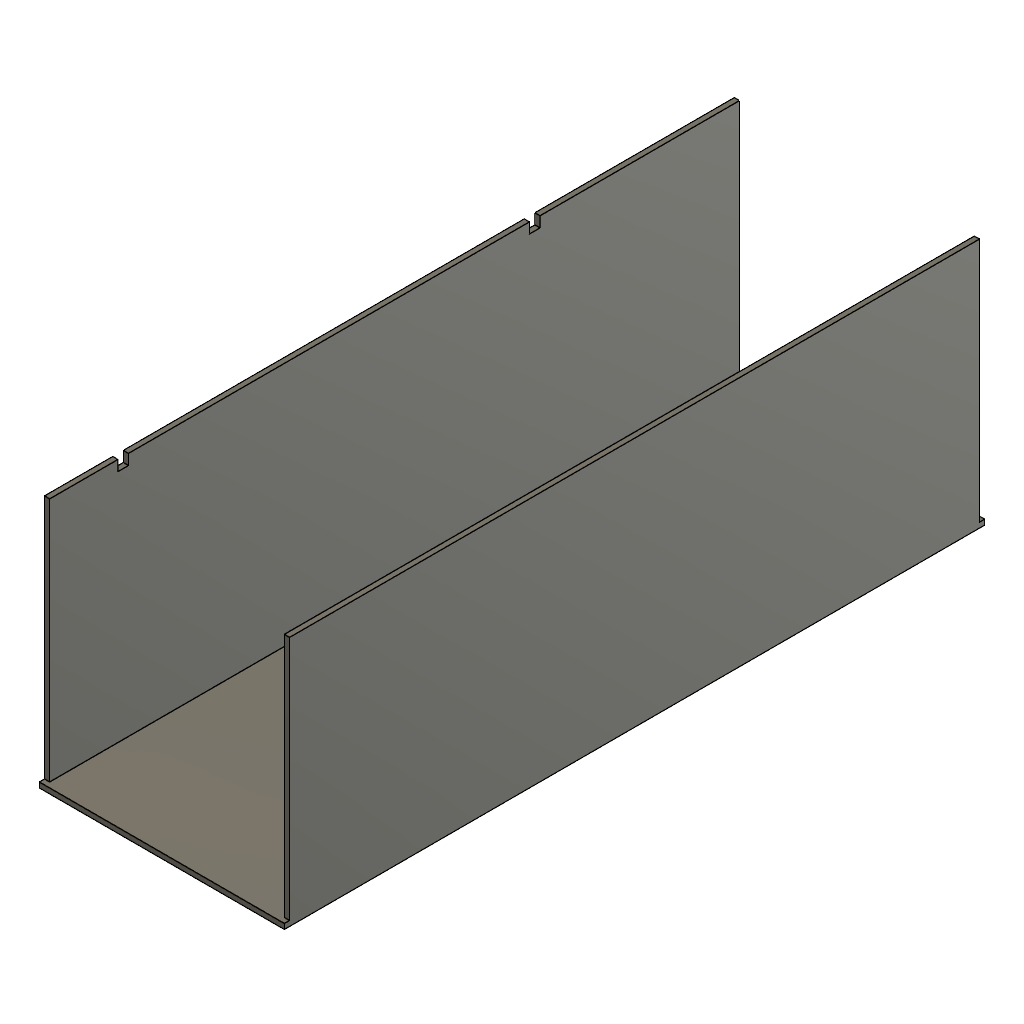
cooling-enclosure-assembly (Autodesk Fusion 360 archive; units mm, degrees)
design "Enclosure Base"
part number: 2026-11-27-19-35-51-728
Autodesk Fusion 360 part; units mm, degrees
sketch "Sketch1" plane through (0, 0, 0) normal (0, 1, 0) x (1, 0, 0)
  line L0 (70, 200) -> (-70, 200)
  line L1 (-70, 200) -> (-70, -200)
  line L2 (-70, -200) -> (70, -200)
  line L3 (70, -200) -> (70, 200)
  line L4 (70, 200) -> (-70, -200) construction
  line L5 (-70, 200) -> (70, -200) construction
  dimension "d1" = 140
  dimension "d2" = 400
  constraint horizontal L0
  constraint perpendicular L0 L1
  constraint parallel L0 L2
  constraint parallel L1 L3
  constraint coincident L4 origin
  constraint coincident L5 origin
  measures "d1" distance of L1.end L2.end
extrude "Extrude1" add sketch "Sketch1" along normal blind 3
sketch "Sketch2" plane through (0, 0, 0) normal (1, 0, 0) x (0, 0, -1)
sketch "Sketch3" plane through (0, 3, 0) normal (0, 1, 0) x (-1, 0, 0)
  line L0 (-70, 200) -> (-70, -200)
  line L1 (-70, -200) -> (70, -200)
  line L2 (70, -200) -> (70, 200)
  line L3 (70, 200) -> (-70, 200)
  line L4 (-67, 197) -> (-70, 197)
  line L5 (-70, 197) -> (-70, -197)
  line L6 (-70, -197) -> (-67, -197)
  line L7 (-67, -197) -> (-67, 197)
  line L8 (-67, 197) -> (-70, -197) construction
  line L9 (-70, 197) -> (-67, -197) construction
  line L10 (67, -197) -> (67, 197)
  line L11 (70, 197) -> (70, -197)
  line L12 (67, 197) -> (70, 197)
  line L13 (70, -197) -> (67, -197)
  point P0 (-68.5, 0)
  dimension "d5" = 3
  dimension "d6" = 394
  constraint horizontal L4
  constraint perpendicular L4 L5
  constraint parallel L4 L6
  constraint parallel L5 L7
  constraint coincident L8 P0
  constraint coincident L9 P0
  measures "d5" distance of L5.end L6.end
  measures "d6" distance of L4.end L5.end
extrude "Extrude2" add sketch "Sketch3" along normal blind 140 contours L0 L4 L5 L6 L7 | L2 L10 L11 L12 L13
sketch "Sketch4" plane through (-67, 0, 0) normal (1, 0, 0) x (0, 0, -1)
  line L0 (-197, 3) -> (197, 3)
  line L1 (197, 3) -> (197, 143)
  line L2 (197, 143) -> (-197, 143)
  line L3 (-197, 143) -> (-197, 3)
  line L4 (83, 137) -> (77, 137)
  line L5 (77, 137) -> (77, 149)
  line L6 (77, 149) -> (83, 149)
  line L7 (83, 149) -> (83, 137)
  line L8 (83, 137) -> (77, 149) construction
  line L9 (77, 137) -> (83, 149) construction
  line L10 (-152, 137) -> (-158, 137)
  line L11 (-158, 137) -> (-158, 149)
  line L12 (-158, 149) -> (-152, 149)
  line L13 (-152, 149) -> (-152, 137)
  line L14 (-152, 137) -> (-158, 149) construction
  line L15 (-158, 137) -> (-152, 149) construction
  point P0 (80, 143)
  point P1 (-155, 143)
  dimension "d11" = 6
  dimension "d12" = 12
  dimension "d13" = 6
  dimension "d14" = 12
  constraint horizontal L4
  constraint perpendicular L4 L5
  constraint parallel L4 L6
  constraint parallel L5 L7
  constraint coincident L8 P0
  constraint coincident L9 P0
  constraint horizontal L10
  constraint perpendicular L10 L11
  constraint parallel L10 L12
  constraint parallel L11 L13
  constraint coincident L14 P1
  constraint coincident L15 P1
  measures "d11" distance of L5.end L6.end
  measures "d12" distance of L4.end L5.end
  measures "d13" distance of L11.end L12.end
  measures "d14" distance of L10.end L11.end
extrude "Extrude3" cut sketch "Sketch4" against normal blind 3 contours L2 L10 L11 L13 | L2 L4 L5 L7

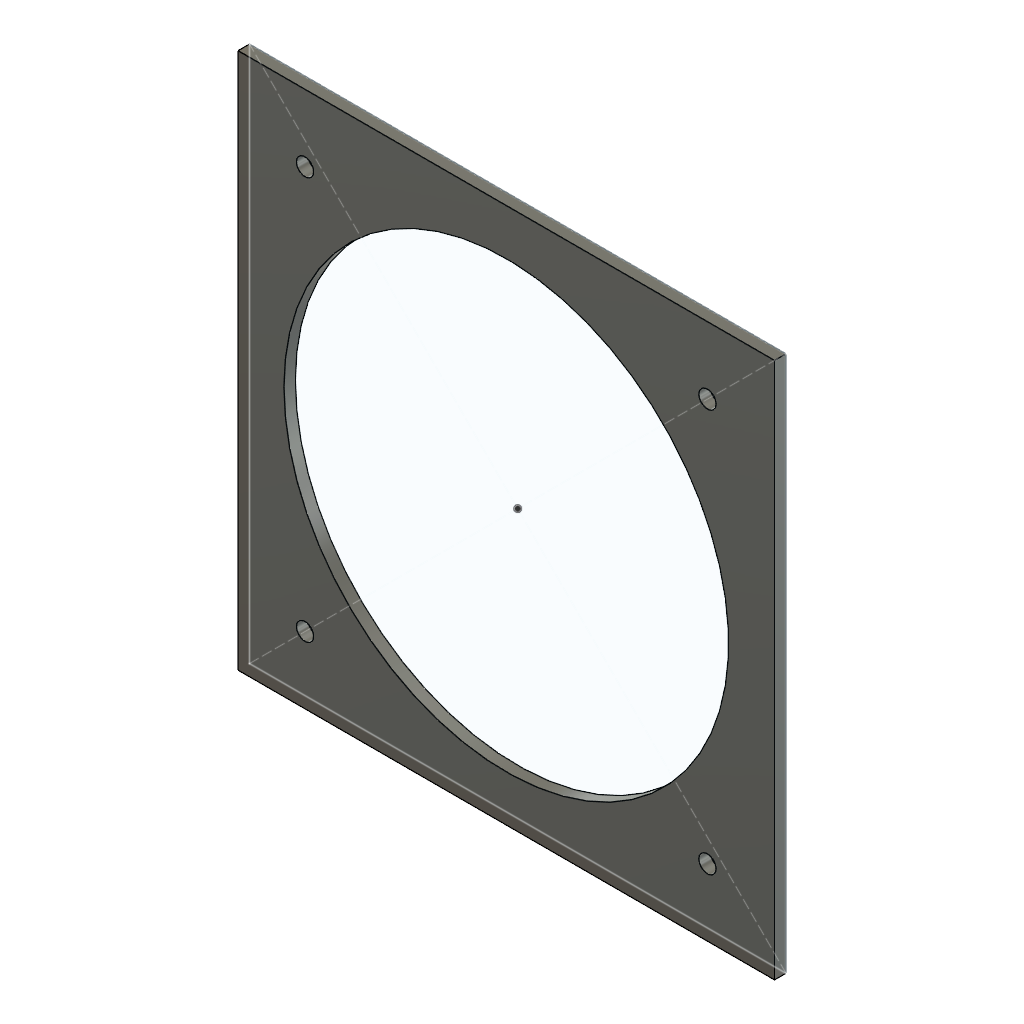
design "Fan End Panel"
part number: 2026-11-27-18-27-05-652
Autodesk Fusion 360 part; units mm, degrees
sketch "Sketch1" plane through (0, 0, 0) normal (0, 1, 0) x (1, 0, 0)
  line L0 (-25, 25) -> (-25, -30)
  line L1 (-25, -30) -> (21.9089, -30)
  line L2 (21.9089, -30) -> (21.9089, 25)
  line L3 (21.9089, 25) -> (-25, 25)
  constraint vertical L0
  constraint perpendicular L0 L1
  constraint perpendicular L1 L2
  constraint perpendicular L0 L3
sketch "Sketch2" plane through (0, 0, 0) normal (0, 1, 0) x (1, 0, 0)
sketch "Sketch3" plane through (0, 0, 0) normal (0, 0, 1) x (1, 0, 0)
sketch "Sketch4" plane through (0, 0, 0) normal (0, 1, 0) x (1, 0, 0)
sketch "Sketch5" plane through (0, 0, 0) normal (0, 0, 1) x (1, 0, 0)
  line L0 (-70, -70) -> (70, -70)
  line L1 (70, -70) -> (70, 70)
  line L2 (70, 70) -> (-70, 70)
  line L3 (-70, 70) -> (-70, -70)
  line L4 (-70, -70) -> (70, 70) construction
  line L5 (70, -70) -> (-70, 70) construction
  dimension "d7" = 140
  dimension "d8" = 140
  constraint horizontal L0
  constraint perpendicular L0 L1
  constraint parallel L0 L2
  constraint parallel L1 L3
  constraint coincident L4 origin
  constraint coincident L5 origin
  measures "d7" distance of L1.end L2.end
  measures "d8" distance of L0.end L1.end
extrude "Extrude2" add sketch "Sketch5" along normal blind 3
sketch "Sketch6" plane through (0, 0, 0) normal (0, 0, -1) x (-1, 0, 0)
  line L0 (70, -70) -> (70, 70)
  line L1 (70, 70) -> (-70, 70)
  line L2 (-70, 70) -> (-70, -70)
  line L3 (-70, -70) -> (70, -70)
sketch "Sketch7" plane through (0, 0, 0) normal (0, 1, 0) x (1, 0, 0)
  line L0 (52.5, 52.5) -> (-52.5, 52.5) construction
  line L1 (-52.5, 52.5) -> (-52.5, -52.5) construction
  line L2 (-52.5, -52.5) -> (52.5, -52.5) construction
  line L3 (52.5, -52.5) -> (52.5, 52.5) construction
  line L4 (52.5, 52.5) -> (-52.5, -52.5) construction
  line L5 (-52.5, 52.5) -> (52.5, -52.5) construction
  dimension "d11" = 105
  dimension "d12" = 105
  constraint horizontal L0
  constraint perpendicular L0 L1
  constraint parallel L0 L2
  constraint parallel L1 L3
  constraint coincident L4 origin
  constraint coincident L5 origin
  measures "d11" distance of L1.end L2.end
  measures "d12" distance of L0.end L1.end
sketch "Sketch8" plane through (0, 0, 3) normal (0, 0, 1) x (1, 0, 0)
  line L0 (-70, 70) -> (-70, -70)
  line L1 (-70, -70) -> (70, -70)
  line L2 (70, -70) -> (70, 70)
  line L3 (70, 70) -> (-70, 70)
  line L4 (52.5, -52.5) -> (-52.5, -52.5) construction
  line L5 (-52.5, -52.5) -> (-52.5, 52.5) construction
  line L6 (-52.5, 52.5) -> (52.5, 52.5) construction
  line L7 (52.5, 52.5) -> (52.5, -52.5) construction
  line L8 (52.5, -52.5) -> (-52.5, 52.5) construction
  line L9 (-52.5, -52.5) -> (52.5, 52.5) construction
  circle A0 centre (52.5, -52.5) radius 2.25
  circle A1 centre (52.5, 52.5) radius 2.25
  circle A2 centre (-52.5, 52.5) radius 2.25
  circle A3 centre (-52.5, -52.5) radius 2.25
  circle A4 centre (0, 0) radius 58
  dimension "d13" = 105
  dimension "d14" = 105
  dimension "d15" = 4.5
  dimension "d16" = 4.5
  dimension "d17" = 4.5
  dimension "d18" = 4.5
  dimension "d19" = 116
  constraint horizontal L4
  constraint perpendicular L4 L5
  constraint parallel L4 L6
  constraint parallel L5 L7
  constraint coincident L8 A4.centre
  constraint coincident L9 A4.centre
  constraint coincident A4.centre origin
  constraint coincident L4.start L7.end
  constraint coincident L6.end L7.start
  constraint coincident L5.end L6.start
  constraint coincident L4.end L5.start
  measures "d13" distance of L5.end L6.end
  measures "d14" distance of L4.end L5.end
  measures "d15" diameter of A0
  measures "d16" diameter of A1
  measures "d17" diameter of A2
  measures "d18" diameter of A3
  measures "d19" diameter of A4
extrude "Extrude3" cut sketch "Sketch8" against normal through all contours A0 | A1 | A2 | A3 | A4

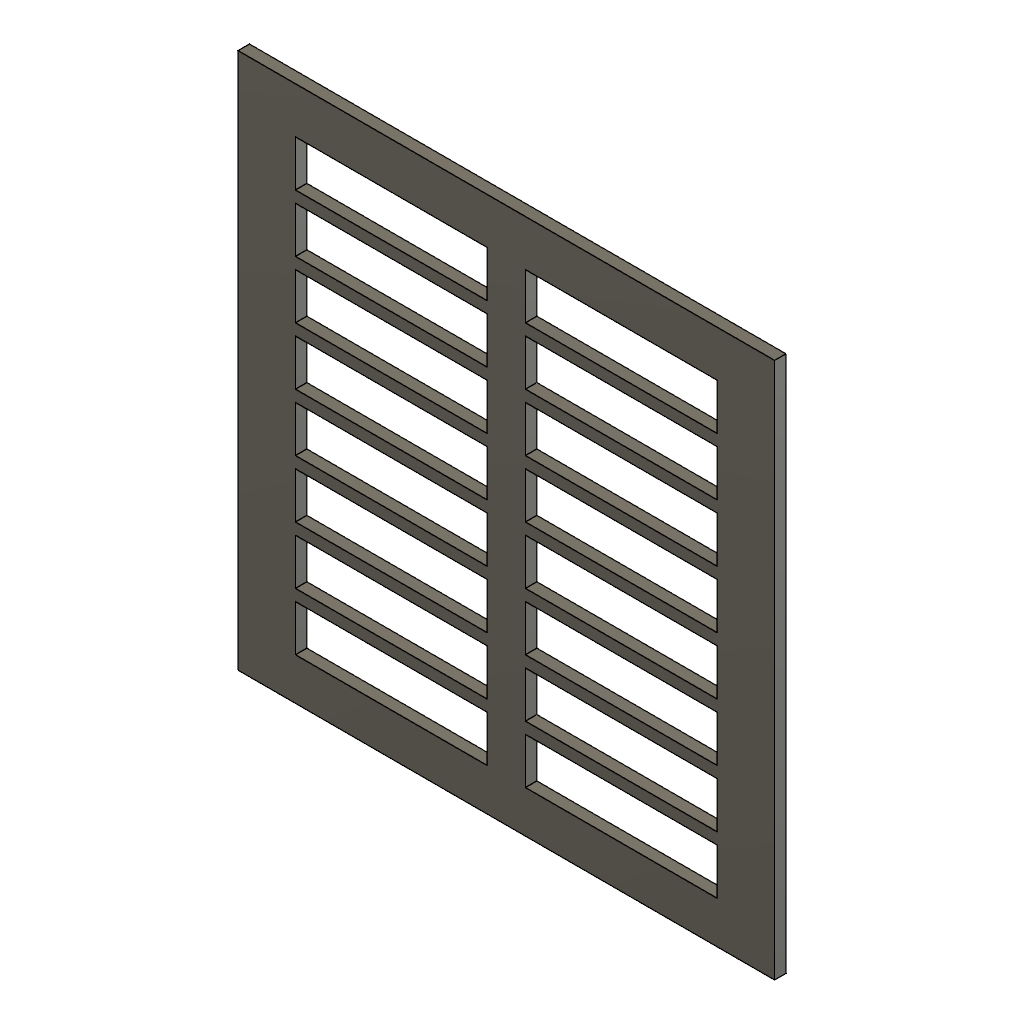
design "Intake Plate"
part number: 2026-11-27-21-02-50-223
Autodesk Fusion 360 part; units mm, degrees
sketch "Sketch1" plane through (0, 0, 0) normal (0, 1, 0) x (1, 0, 0)
sketch "Sketch2" plane through (0, 0, 0) normal (0, 0, 1) x (1, 0, 0)
  line L0 (70, 70) -> (-70, 70)
  line L1 (-70, 70) -> (-70, -70)
  line L2 (-70, -70) -> (70, -70)
  line L3 (70, -70) -> (70, 70)
  line L4 (70, 70) -> (-70, -70) construction
  line L5 (-70, 70) -> (70, -70) construction
  dimension "d1" = 140
  dimension "d2" = 140
  constraint horizontal L0
  constraint perpendicular L0 L1
  constraint parallel L0 L2
  constraint parallel L1 L3
  constraint coincident L4 origin
  constraint coincident L5 origin
  measures "d1" distance of L1.end L2.end
  measures "d2" distance of L0.end L1.end
extrude "Extrude1" add sketch "Sketch2" along normal blind 3
sketch "Sketch3" plane through (0, 0, 3) normal (0, 0, 1) x (1, 0, 0)
  line L0 (70, -70) -> (70, 70)
  line L1 (70, 70) -> (-70, 70)
  line L2 (-70, 70) -> (-70, -70)
  line L3 (-70, -70) -> (70, -70)
  line L4 (-55, 58) -> (-5, 58)
  line L5 (-5, 58) -> (-5, 46)
  line L6 (-5, 46) -> (-55, 46)
  line L7 (-55, 46) -> (-55, 58)
  line L8 (55, 58) -> (55, 46)
  line L9 (5, 58) -> (55, 58)
  line L10 (5, 46) -> (5, 58)
  line L11 (55, 46) -> (5, 46)
  line L12 (-5, 43) -> (-5, 31)
  line L13 (-55, 43) -> (-5, 43)
  line L14 (-55, 31) -> (-55, 43)
  line L15 (-5, 31) -> (-55, 31)
  line L16 (55, 43) -> (55, 31)
  line L17 (5, 43) -> (55, 43)
  line L18 (5, 31) -> (5, 43)
  line L19 (55, 31) -> (5, 31)
  line L20 (-5, 28) -> (-5, 16)
  line L21 (-55, 28) -> (-5, 28)
  line L22 (-55, 16) -> (-55, 28)
  line L23 (-5, 16) -> (-55, 16)
  line L24 (55, 28) -> (55, 16)
  line L25 (5, 28) -> (55, 28)
  line L26 (5, 16) -> (5, 28)
  line L27 (55, 16) -> (5, 16)
  line L28 (-5, 13) -> (-5, 1)
  line L29 (-55, 13) -> (-5, 13)
  line L30 (-55, 1) -> (-55, 13)
  line L31 (-5, 1) -> (-55, 1)
  line L32 (55, 13) -> (55, 1)
  line L33 (5, 13) -> (55, 13)
  line L34 (5, 1) -> (5, 13)
  line L35 (55, 1) -> (5, 1)
  line L36 (-5, -2) -> (-5, -14)
  line L37 (-55, -2) -> (-5, -2)
  line L38 (-55, -14) -> (-55, -2)
  line L39 (-5, -14) -> (-55, -14)
  line L40 (55, -2) -> (55, -14)
  line L41 (5, -2) -> (55, -2)
  line L42 (5, -14) -> (5, -2)
  line L43 (55, -14) -> (5, -14)
  line L44 (-5, -17) -> (-5, -29)
  line L45 (-55, -17) -> (-5, -17)
  line L46 (-55, -29) -> (-55, -17)
  line L47 (-5, -29) -> (-55, -29)
  line L48 (55, -17) -> (55, -29)
  line L49 (5, -17) -> (55, -17)
  line L50 (5, -29) -> (5, -17)
  line L51 (55, -29) -> (5, -29)
  line L52 (-5, -32) -> (-5, -44)
  line L53 (-55, -32) -> (-5, -32)
  line L54 (-55, -44) -> (-55, -32)
  line L55 (-5, -44) -> (-55, -44)
  line L56 (55, -32) -> (55, -44)
  line L57 (5, -32) -> (55, -32)
  line L58 (5, -44) -> (5, -32)
  line L59 (55, -44) -> (5, -44)
  line L60 (-5, -47) -> (-5, -59)
  line L61 (-55, -47) -> (-5, -47)
  line L62 (-55, -59) -> (-55, -47)
  line L63 (-5, -59) -> (-55, -59)
  line L64 (55, -47) -> (55, -59)
  line L65 (5, -47) -> (55, -47)
  line L66 (5, -59) -> (5, -47)
  line L67 (55, -59) -> (5, -59)
  dimension "d5" = 50
  dimension "d6" = 12
  dimension "d7" = 15
  dimension "d8" = 12
  dimension "d11" = 60
  dimension "d12" = -15
  constraint horizontal L4
  constraint vertical L5
  constraint horizontal L6
  constraint vertical L7
  measures "d5" distance of L4.start L4.end
  measures "d6" distance of L4.start L6.end
  measures "d7" distance of L2 L7
  measures "d8" distance of L1 L4
extrude "Extrude2" cut sketch "Sketch3" against normal through all contours L4 L5 L6 L7 | L8 L9 L10 L11 | L12 L13 L14 L15 | L16 L17 L18 L19 | L20 L21 L22 L23 | L24 L25 L26 L27 | L28 L29 L30 L31 | L32 L33 L34 L35 | L36 L37 L38 L39 | L40 L41 L42 L43 | L44 L45 L46 L47 | L48 L49 L50 L51 | L52 L53 L54 L55 | L56 L57 L58 L59 | L60 L61 L62 L63 | L64 L65 L66 L67

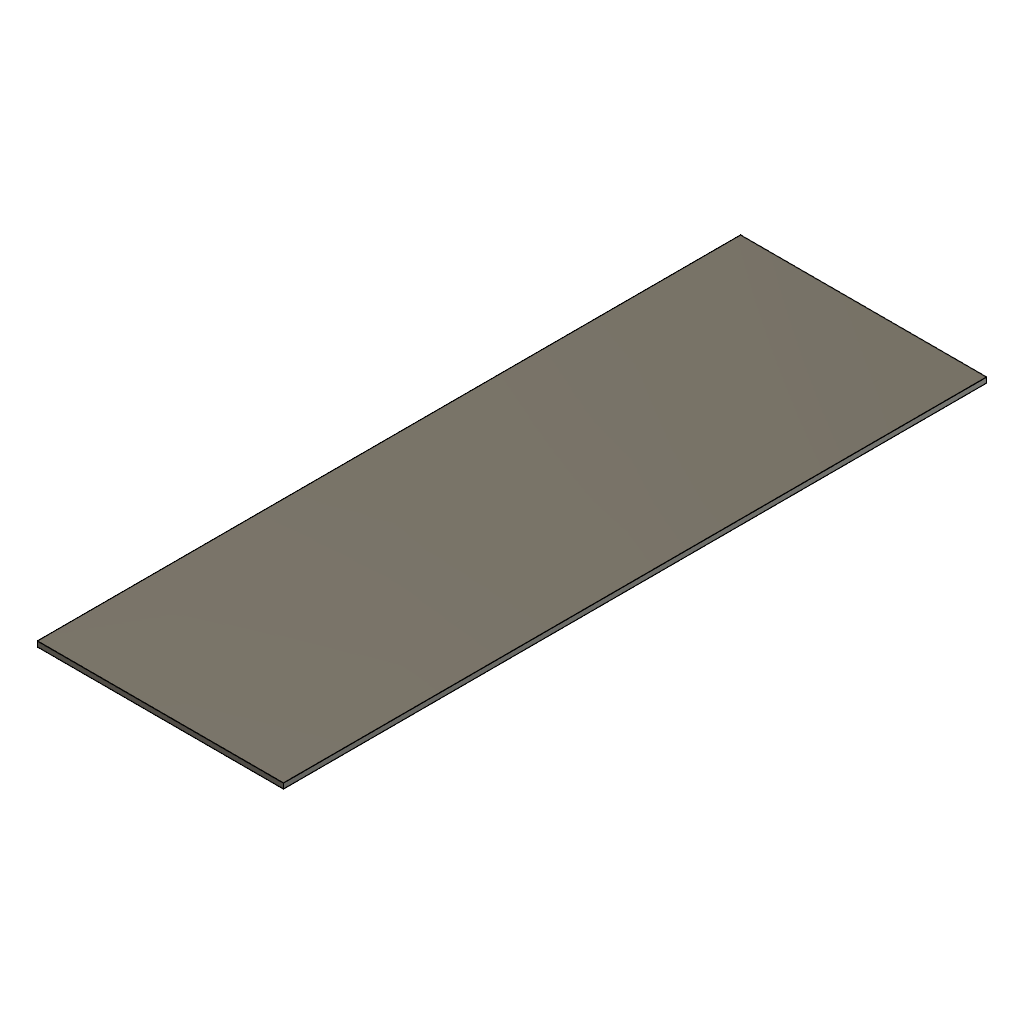
design "Removable Lid"
part number: 2026-11-27-21-18-04-278
Autodesk Fusion 360 part; units mm, degrees
sketch "Sketch1" plane through (0, 0, 0) normal (0, 1, 0) x (1, 0, 0)
  line L0 (-70, 200) -> (70, 200)
  line L1 (70, 200) -> (70, -200)
  line L2 (70, -200) -> (-70, -200)
  line L3 (-70, -200) -> (-70, 200)
  line L4 (-70, 200) -> (70, -200) construction
  line L5 (70, 200) -> (-70, -200) construction
  dimension "d1" = 140
  dimension "d2" = 400
  constraint horizontal L0
  constraint perpendicular L0 L1
  constraint parallel L0 L2
  constraint parallel L1 L3
  constraint coincident L4 origin
  constraint coincident L5 origin
  measures "d1" distance of L1.end L2.end
extrude "Extrude1" add sketch "Sketch1" along normal blind 3
